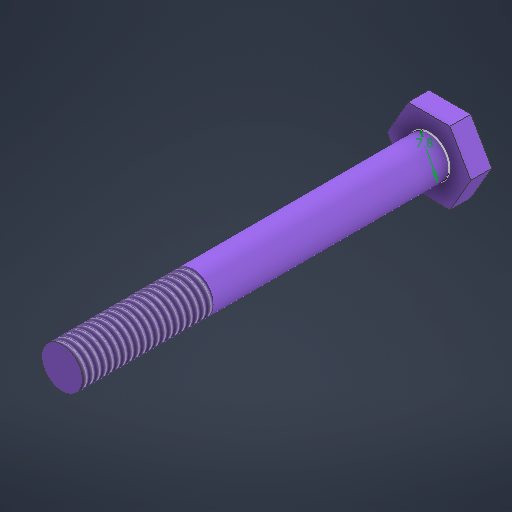
# Autodesk Inventor part: PERNO 2 EXAMEN PARCIAL
Saved by Autodesk Inventor 2026.4 (Build 304435000, 435)
## iProperties
Created: 2026-10-30
Part Number: PERNO 2 EXAMEN PARCIAL
Material: Genérico
Document SubType Name: Modeling
Designer: elbis
Density: 1 g/cm^3
Appearance: Valor por defecto
Author: elbis
Autodesk Inventor part; units mm, degrees
ref_plane "YZ Plane" through (0, 0, 0) normal (1, 0, 0) x (0, 1, 0)
ref_plane "XZ Plane" through (0, 0, 0) normal (0, 1, 0) x (-1, 0, 0)
sketch "Boceto1" plane through (0, 0, 0) normal (0, 0, 1) x (1, 0, 0)
  line L0 (0, 0) -> (8, 0)
  line L1 (0, 0) -> (-8, 0)
  line L2 (-8, 0) -> (-4, 6.9282)
  line L3 (-4, 6.9282) -> (4, 6.9282)
  line L4 (4, 6.9282) -> (8, 0)
  line L5 (8, 0) -> (4, -6.9282)
  line L6 (4, -6.9282) -> (-4, -6.9282)
  line L7 (-4, -6.9282) -> (-8, 0)
  dimension "d0" = 8
  dimension "d1" = 8
  constraints: 16 end point, 2 horizontal, 1 coincident, 13 other
  measures "d0" distance of L0.start L0.end
  measures "d1" distance of L0.start L1.end
extrude "Extrusión1" add sketch "Boceto1" along normal blind 4
sketch "Boceto2" plane through (0, 0, 4) normal (0, 0, 1) x (1, 0, 0)
  circle A0 centre (0, 0) radius 3.9
  dimension "d4" = 7.8
  constraints: 1 centre point, 1 coincident
  measures "d4" diameter of A0
ref_plane "Plano de trabajo1" through (0, 0, 49) normal (0, 0, 1) x (1, 0, 0)
sketch "Boceto3" plane through (0, 0, 49) normal (0, 0, 1) x (1, 0, 0)
  circle A0 centre (0, 0) radius 3.9
  constraints: 1 centre point, 1 coincident
extrude "Extrusión3" add sketch "Boceto3" along normal blind 25
sketch "Boceto4" plane through (0, 0, 4) normal (0, 0, 1) x (1, 0, 0)
  point P0 (0, 0)
sketch "Boceto5" plane through (0, 0, 4) normal (0, 0, 1) x (1, 0, 0)
  circle A0 centre (0, 0) radius 3.9
  dimension "d11" = 7.8
  constraints: 1 centre point, 1 coincident
  measures "d11" diameter of A0
extrude "Extrusión4" add sketch "Boceto5" along normal blind 45
thread "Rosca3" size "M8x1.25" class "6g" standard "ANSI Metric M Profile" length 25
